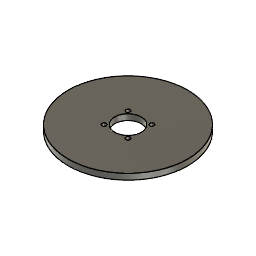
Flansch_Zapfsaeule_Zaehler (Autodesk Fusion 360 design; units mm, degrees)
Autodesk Fusion 360 part; units mm, degrees
sketch "Skizze1" plane through (0, 0, 0) normal (0, 0, 1) x (1, 0, 0)
  circle A0 centre (0, 0) radius 11.1
  circle A1 centre (0, 0) radius 50
  line L0 (10, 10) -> (-10, 10) construction
  line L1 (-10, 10) -> (-10, -10) construction
  line L2 (-10, -10) -> (10, -10) construction
  line L3 (10, -10) -> (10, 10) construction
  line L4 (10, 10) -> (-10, -10) construction
  line L5 (-10, 10) -> (10, -10) construction
  circle A2 centre (-10, 10) radius 1.75
  circle A3 centre (10, 10) radius 1.75
  circle A4 centre (-10, -10) radius 1.75
  circle A5 centre (10, -10) radius 1.75
  dimension "d1" = 20
  dimension "d2" = 20
  dimension "d3" = 22.2
  dimension "d4" = 3.5
  dimension "d7" = 20
  dimension "d8" = -20
  dimension "d11" = 100
  constraint coincident A0.centre A1.centre
  constraint horizontal L0
  constraint perpendicular L0 L1
  constraint parallel L0 L2
  constraint parallel L1 L3
  constraint coincident L4 A0.centre
  constraint coincident L5 A0.centre
  constraint coincident L0.end L1.start
  measures "d1" distance of L0.start L2.end
  measures "d2" distance of L0.start L0.end
  measures "d3" diameter of A0
  measures "d4" diameter of A2
  measures "d11" diameter of A1
extrude "Extrusion1" add sketch "Skizze1" along normal blind 5
